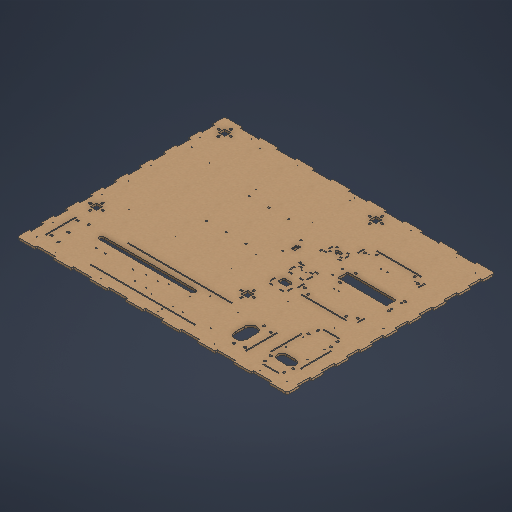
# Autodesk Inventor part: upper_base
Saved by Autodesk Inventor 2027.1 (Build 311270010, 270A)
## iProperties
Created: 2026-11-15
Part Number: upper_base
Material: MDF Medium Density Fiberboard
Document SubType Name: Modeling
Designer: SDS Scholar
Density: 0.8 g/cm^3
Appearance: Cardboard - Corrugated
Author: SDS Scholar
Autodesk Inventor part; units mm, degrees
(part 1 of 3)
ref_plane "YZ Plane" through (0, 0, 0) normal (1, 0, 0) x (0, 1, 0)
ref_plane "XZ Plane" through (0, 0, 0) normal (0, 1, 0) x (-1, 0, 0)
ref_plane "XY Plane" through (0, 0, 0) normal (0, 0, 1) x (1, 0, 0)
sketch "Sketch1" plane through (0, 0, 0) normal (0, 1, 0) x (-1, 0, 0)
  line L0 (-442.5, 340) -> (442.5, 340)
  line L1 (442.5, 340) -> (442.5, -340)
  line L2 (442.5, -340) -> (-442.5, -340)
  line L3 (-442.5, -340) -> (-442.5, 340)
  line L4 (-442.5, 340) -> (442.5, -340) construction
  line L5 (442.5, 340) -> (-442.5, -340) construction
  point P0 (0, 0)
  dimension "d0" = 680
  dimension "d1" = 885
  constraints: 12 end point, 2 midpoint, 2 parallel, 1 horizontal, 1 perpendicular
  measures "d0" distance of L0.end L1.end
  measures "d1" distance of L1.end L2.end
extrude "Extrusion1" add sketch "Sketch1" along normal blind 7
sketch "Sketch3" plane through (0, 7, 0) normal (0, 1, 0) x (1, 0, 0)
  line L0 (442.5, 340) -> (-442.5, 340) projected
  line L1 (-442.5, 340) -> (-442.5, -340) projected
  line L2 (-442.5, -340) -> (442.5, -340) projected
  line L3 (442.5, -340) -> (442.5, 340) projected
  line L4 (-407.5, 305) -> (107.5, 305)
  line L5 (107.5, 305) -> (107.5, -135)
  line L6 (107.5, -135) -> (-407.5, -135)
  line L7 (-407.5, -135) -> (-407.5, 305)
  line L8 (-407.5, 305) -> (-387.5, 305)
  line L9 (-387.5, 305) -> (-387.5, 285)
  line L10 (-387.5, 285) -> (-407.5, 285)
  line L11 (-407.5, 285) -> (-407.5, 305)
  line L12 (-407.5, 305) -> (-387.5, 285) construction
  line L13 (-387.5, 305) -> (-407.5, 285) construction
  line L14 (-397.5, 313.5) -> (-397.5, 316.5) construction
  line L15 (-394.6, 313.5) -> (-394.6, 316.5)
  line L16 (-400.4, 316.5) -> (-400.4, 313.5)
  arc A0 (-400.4, 313.5) -> (-394.6, 313.5) centre (-397.5, 313.5) ccw
  arc A1 (-394.6, 316.5) -> (-400.4, 316.5) centre (-397.5, 316.5) ccw
  line L17 (-407.5, 295) -> (-387.5, 295) construction
  line L18 (-397.5, 285) -> (-397.5, 305) construction
  line L19 (-397.5, 276.5) -> (-397.5, 273.5) construction
  line L20 (-394.6, 276.5) -> (-394.6, 273.5)
  line L21 (-400.4, 273.5) -> (-400.4, 276.5)
  arc A2 (-394.6, 276.5) -> (-400.4, 276.5) centre (-397.5, 276.5) ccw
  arc A3 (-400.4, 273.5) -> (-394.6, 273.5) centre (-397.5, 273.5) ccw
  line L22 (-416, 295) -> (-419, 295) construction
  line L23 (-416, 297.9) -> (-419, 297.9)
  line L24 (-419, 292.1) -> (-416, 292.1)
  arc A4 (-416, 292.1) -> (-416, 297.9) centre (-416, 295) ccw
  arc A5 (-419, 297.9) -> (-419, 292.1) centre (-419, 295) ccw
  line L25 (-379, 295) -> (-376, 295) construction
  line L26 (-379, 297.9) -> (-376, 297.9)
  line L27 (-376, 292.1) -> (-379, 292.1)
  arc A6 (-379, 297.9) -> (-379, 292.1) centre (-379, 295) ccw
  arc A7 (-376, 292.1) -> (-376, 297.9) centre (-376, 295) ccw
  line L28 (-387.5, -135) -> (-407.5, -135)
  line L29 (-387.5, -115) -> (-387.5, -135)
  line L30 (-407.5, -115) -> (-387.5, -115)
  line L31 (-407.5, -135) -> (-407.5, -115)
  arc A8 (-400.4, -106.5) -> (-394.6, -106.5) centre (-397.5, -106.5) ccw
  line L32 (-394.6, -106.5) -> (-394.6, -103.5)
  line L33 (-400.4, -103.5) -> (-400.4, -106.5)
  arc A9 (-394.6, -103.5) -> (-400.4, -103.5) centre (-397.5, -103.5) ccw
  arc A10 (-379, -122.1) -> (-379, -127.9) centre (-379, -125) ccw
  arc A11 (-376, -127.9) -> (-376, -122.1) centre (-376, -125) ccw
  line L34 (-376, -127.9) -> (-379, -127.9)
  line L35 (-379, -122.1) -> (-376, -122.1)
  arc A12 (-394.6, -143.5) -> (-400.4, -143.5) centre (-397.5, -143.5) ccw
  arc A13 (-400.4, -146.5) -> (-394.6, -146.5) centre (-397.5, -146.5) ccw
  line L36 (-400.4, -146.5) -> (-400.4, -143.5)
  line L37 (-394.6, -143.5) -> (-394.6, -146.5)
  arc A14 (-416, -127.9) -> (-416, -122.1) centre (-416, -125) ccw
  arc A15 (-419, -122.1) -> (-419, -127.9) centre (-419, -125) ccw
  line L38 (-416, -122.1) -> (-419, -122.1)
  line L39 (-419, -127.9) -> (-416, -127.9)
  line L40 (107.5, 285) -> (87.5, 285)
  line L41 (107.5, 305) -> (107.5, 285)
  line L42 (87.5, 305) -> (107.5, 305)
  line L43 (87.5, 285) -> (87.5, 305)
  arc A16 (94.6, 313.5) -> (100.4, 313.5) centre (97.5, 313.5) ccw
  line L44 (100.4, 313.5) -> (100.4, 316.5)
  line L45 (94.6, 316.5) -> (94.6, 313.5)
  arc A17 (100.4, 316.5) -> (94.6, 316.5) centre (97.5, 316.5) ccw
  arc A18 (116, 297.9) -> (116, 292.1) centre (116, 295) ccw
  arc A19 (119, 292.1) -> (119, 297.9) centre (119, 295) ccw
  line L46 (119, 292.1) -> (116, 292.1)
  line L47 (116, 297.9) -> (119, 297.9)
  arc A20 (100.4, 276.5) -> (94.6, 276.5) centre (97.5, 276.5) ccw
  arc A21 (94.6, 273.5) -> (100.4, 273.5) centre (97.5, 273.5) ccw
  line L48 (94.6, 273.5) -> (94.6, 276.5)
  line L49 (100.4, 276.5) -> (100.4, 273.5)
  arc A22 (79, 292.1) -> (79, 297.9) centre (79, 295) ccw
  arc A23 (76, 297.9) -> (76, 292.1) centre (76, 295) ccw
  line L50 (79, 297.9) -> (76, 297.9)
  line L51 (76, 292.1) -> (79, 292.1)
  line L52 (107.5, -135) -> (87.5, -135)
  line L53 (107.5, -115) -> (107.5, -135)
  line L54 (87.5, -115) -> (107.5, -115)
  line L55 (87.5, -135) -> (87.5, -115)
  arc A24 (94.6, -106.5) -> (100.4, -106.5) centre (97.5, -106.5) ccw
  line L56 (100.4, -106.5) -> (100.4, -103.5)
  line L57 (94.6, -103.5) -> (94.6, -106.5)
  arc A25 (100.4, -103.5) -> (94.6, -103.5) centre (97.5, -103.5) ccw
  arc A26 (116, -122.1) -> (116, -127.9) centre (116, -125) ccw
  arc A27 (119, -127.9) -> (119, -122.1) centre (119, -125) ccw
  line L58 (119, -127.9) -> (116, -127.9)
  line L59 (116, -122.1) -> (119, -122.1)
  arc A28 (100.4, -143.5) -> (94.6, -143.5) centre (97.5, -143.5) ccw
  arc A29 (94.6, -146.5) -> (100.4, -146.5) centre (97.5, -146.5) ccw
  line L60 (94.6, -146.5) -> (94.6, -143.5)
  line L61 (100.4, -143.5) -> (100.4, -146.5)
  arc A30 (79, -127.9) -> (79, -122.1) centre (79, -125) ccw
  arc A31 (76, -122.1) -> (76, -127.9) centre (76, -125) ccw
  line L62 (79, -122.1) -> (76, -122.1)
  line L63 (76, -127.9) -> (79, -127.9)
  point P0 (0, 0)
  point P1 (-397.5, 295)
  point P2 (-397.5, 315)
  point P3 (-397.5, 275)
  point P4 (-417.5, 295)
  point P5 (-397.5, 295)
  point P6 (-377.5, 295)
  point P7 (-397.5, -135)
  point P8 (-387.5, -125)
  point P9 (-397.5, -115)
  point P10 (-407.5, -125)
  point P11 (97.5, 285)
  point P12 (107.5, 295)
  point P13 (97.5, 305)
  point P14 (87.5, 295)
  point P15 (97.5, -135)
  point P16 (107.5, -125)
  point P17 (97.5, -115)
  point P18 (87.5, -125)
  point P19 (87.5, 305)
  point P20 (107.5, 285)
  point P21 (87.5, -135)
  point P22 (107.5, -115)
  point P23 (-407.5, -115)
  point P24 (-407.5, 285)
  dimension "d6" = 35
  dimension "d7" = 35
  dimension "d8" = 440
  dimension "d9" = 515
  dimension "d10" = 20
  dimension "d11" = 20
  dimension "d12" = 3
  dimension "d13" = 5.8
  dimension "d14" = 8.5
  dimension "d15" = 3
  dimension "d16" = 5.8
  dimension "d17" = 8.5
  dimension "d20" = 420
  dimension "d23" = 495
  constraints: 128 end point, 64 point on circle, 32 centre point, 14 symmetric about line, 9 midpoint, 8 tangent, 6 parallel, 4 horizontal, 3 perpendicular, 1 horizontal alignment, 1 vertical, 1 vertical alignment, 160 other
  measures "d6" distance between parallel lines of L0 L4
  measures "d7" distance between parallel lines of L1 L7
  measures "d8" distance of L6.end L4.start
  measures "d9" distance of L4.start L4.end
  measures "d10" distance of L4.start L10.end
  measures "d11" distance of L4.start L8.end
  measures "d12" distance of L14.start L14.end
  measures "d13" diameter of A1
  measures "d14" distance from line of L4 L14.start
  measures "d15" distance of L22.start L22.end
  measures "d16" diameter of A5
  measures "d17" distance from line of L7 L22.start
  measures "d20" distance of L9.end L28.start
  measures "d23" distance of L9.end L40.start
extrude "Extrusion2" cut sketch "Sketch3" against normal through all contours L4 L9 L10 L7 | L4 L5 L40 L43 | L30 L29 L6 L7 | L5 L6 L55 L54 | A0 L16 A1 L15 | L20 A3 L21 A2 | A4 L24 A5 L23 | L26 A7 L27 A6 | L33 A9 L32 A8 | L35 A11 L34 A10 | L37 A13 L36 A12 | L39 A15 L38 A14 | L45 A17 L44 A16 | L47 A19 L46 A18 | L49 A21 L48 A20 | L51 A23 L50 A22 | L57 A25 L56 A24 | L59 A27 L58 A26 | L61 A29 L60 A28 | L63 A31 L62 A30
sketch "Sketch4" plane through (0, 7, 0) normal (0, 1, 0) x (1, 0, 0)
  line L0 (-407.5, -135) -> (-407.5, -115) projected
  line L1 (107.5, 305) -> (107.5, 285) projected
  line L2 (-407.5, -135) -> (107.5, -135)
  line L3 (107.5, -135) -> (107.5, 305)
  line L4 (107.5, 305) -> (-407.5, 305)
  line L5 (-407.5, 305) -> (-407.5, -135)
  circle A0 centre (-177.5, 155) radius 2.75
  circle A1 centre (-177.5, 15) radius 2.75
  circle A2 centre (-112.5, 155) radius 2.75
  circle A3 centre (-112.5, 15) radius 2.75
  circle A4 centre (-47.5, 155) radius 2.75
  circle A5 centre (-47.5, 15) radius 2.75
  line L6 (17.5, -135) -> (17.5, 305) construction
  line L7 (17.5, 85) -> (107.5, 85) construction
  circle A6 centre (32.5, 55.5) radius 2.75
  circle A7 centre (32.5, 114.5) radius 2.75
  point P0 (0, 0)
  dimension "d29" = 230
  dimension "d30" = 150
  dimension "d33" = 140
  dimension "d36" = 65
  dimension "d47" = 65
  dimension "d48" = 5.5
  dimension "d49" = 5.5
  dimension "d50" = 59
  dimension "d51" = 15
  constraints: 12 end point, 8 centre point, 2 horizontal, 2 midpoint, 2 parallel, 2 point on line, 2 vertical, 1 perpendicular, 1 symmetric about line, 11 other
  measures "d29" distance from line of L5 A0.centre
  measures "d30" distance from line of L4 A0.centre
  measures "d33" distance of A0.centre A1.centre
  measures "d36" distance of A0.centre A2.centre
  measures "d47" distance from line of L6 A5.centre
  measures "d48" diameter of A6
  measures "d49" diameter of A0
  measures "d50" distance of A7.centre A6.centre
  measures "d51" distance from line of L6 A6.centre
hole "Hole1" at (-177.5, 7, -15) at (-177.5, 7, -155) at (-47.5, 7, -155) at (-112.5, 7, -15) at (-47.5, 7, -15) at (-112.5, 7, -155) at (32.5, 7, -55.5) at (32.5, 7, -114.5) direction (0, -1, 0) diameter 5.5 end through all clearance for "Hex Head Cap Screw ISO 24017" size "M5" standard "ISO"
sketch "Sketch6" plane through (0, 0, 0) normal (0, -1, 0) x (1, 0, 0)
  circle A0 centre (32.5, -114.5) radius 2.75 projected
  circle A1 centre (32.5, -55.5) radius 2.75 projected
  circle A2 centre (-112.5, -155) radius 2.75 projected
  circle A3 centre (-47.5, -15) radius 2.75 projected
  circle A4 centre (-112.5, -15) radius 2.75 projected
  circle A5 centre (-47.5, -155) radius 2.75 projected
  circle A6 centre (-177.5, -155) radius 2.75 projected
  circle A7 centre (-177.5, -15) radius 2.75 projected
  line L0 (-387.5, -305) -> (-407.5, -305) projected
  line L1 (-407.5, -305) -> (-407.5, -285) projected
  line L2 (-407.5, -285) -> (-387.5, -285) projected
  line L3 (-387.5, -285) -> (-387.5, -305) projected
  arc A8 (-419, 127.9) -> (-419, 122.1) centre (-419, 125) ccw projected
  line L4 (-419, 127.9) -> (-416, 127.9) projected
  arc A9 (-416, 122.1) -> (-416, 127.9) centre (-416, 125) ccw projected
  line L5 (-416, 122.1) -> (-419, 122.1) projected
  arc A10 (94.6, 143.5) -> (100.4, 143.5) centre (97.5, 143.5) ccw projected
  line L6 (94.6, 143.5) -> (94.6, 146.5) projected
  arc A11 (100.4, 146.5) -> (94.6, 146.5) centre (97.5, 146.5) ccw projected
  line L7 (100.4, 146.5) -> (100.4, 143.5) projected
  line L8 (107.5, 135) -> (107.5, 115) projected
  line L9 (107.5, 115) -> (87.5, 115) projected
  line L10 (87.5, 115) -> (87.5, 135) projected
  line L11 (87.5, 135) -> (107.5, 135) projected
  arc A12 (94.6, -316.5) -> (100.4, -316.5) centre (97.5, -316.5) ccw projected
  line L12 (94.6, -316.5) -> (94.6, -313.5) projected
  arc A13 (100.4, -313.5) -> (94.6, -313.5) centre (97.5, -313.5) ccw projected
  line L13 (100.4, -313.5) -> (100.4, -316.5) projected
  arc A14 (76, -292.1) -> (76, -297.9) centre (76, -295) ccw projected
  line L14 (76, -292.1) -> (79, -292.1) projected
  arc A15 (79, -297.9) -> (79, -292.1) centre (79, -295) ccw projected
  line L15 (79, -297.9) -> (76, -297.9) projected
  arc A16 (116, 127.9) -> (116, 122.1) centre (116, 125) ccw projected
  line L16 (116, 127.9) -> (119, 127.9) projected
  arc A17 (119, 122.1) -> (119, 127.9) centre (119, 125) ccw projected
  line L17 (119, 122.1) -> (116, 122.1) projected
  line L18 (-407.5, 135) -> (-387.5, 135) projected
  line L19 (-387.5, 135) -> (-387.5, 115) projected
  line L20 (-387.5, 115) -> (-407.5, 115) projected
  line L21 (-407.5, 115) -> (-407.5, 135) projected
  arc A18 (-400.4, 143.5) -> (-394.6, 143.5) centre (-397.5, 143.5) ccw projected
  line L22 (-400.4, 143.5) -> (-400.4, 146.5) projected
  arc A19 (-394.6, 146.5) -> (-400.4, 146.5) centre (-397.5, 146.5) ccw projected
  line L23 (-394.6, 146.5) -> (-394.6, 143.5) projected
  arc A20 (-379, -292.1) -> (-379, -297.9) centre (-379, -295) ccw projected
  line L24 (-379, -292.1) -> (-376, -292.1) projected
  arc A21 (-376, -297.9) -> (-376, -292.1) centre (-376, -295) ccw projected
  line L25 (-376, -297.9) -> (-379, -297.9) projected
  arc A22 (-400.4, -276.5) -> (-394.6, -276.5) centre (-397.5, -276.5) ccw projected
  line L26 (-400.4, -276.5) -> (-400.4, -273.5) projected
  arc A23 (-394.6, -273.5) -> (-400.4, -273.5) centre (-397.5, -273.5) ccw projected
  line L27 (-394.6, -273.5) -> (-394.6, -276.5) projected
  arc A24 (-400.4, 103.5) -> (-394.6, 103.5) centre (-397.5, 103.5) ccw projected
  line L28 (-400.4, 103.5) -> (-400.4, 106.5) projected
  arc A25 (-394.6, 106.5) -> (-400.4, 106.5) centre (-397.5, 106.5) ccw projected
  line L29 (-394.6, 106.5) -> (-394.6, 103.5) projected
  arc A26 (76, 127.9) -> (76, 122.1) centre (76, 125) ccw projected
  line L30 (76, 127.9) -> (79, 127.9) projected
  arc A27 (79, 122.1) -> (79, 127.9) centre (79, 125) ccw projected
  line L31 (79, 122.1) -> (76, 122.1) projected
  arc A28 (116, -292.1) -> (116, -297.9) centre (116, -295) ccw projected
  line L32 (116, -292.1) -> (119, -292.1) projected
  arc A29 (119, -297.9) -> (119, -292.1) centre (119, -295) ccw projected
  line L33 (119, -297.9) -> (116, -297.9) projected
  line L34 (107.5, -285) -> (107.5, -305) projected
  line L35 (107.5, -305) -> (87.5, -305) projected
  line L36 (87.5, -305) -> (87.5, -285) projected
  line L37 (87.5, -285) -> (107.5, -285) projected
  arc A30 (94.6, -276.5) -> (100.4, -276.5) centre (97.5, -276.5) ccw projected
  line L38 (94.6, -276.5) -> (94.6, -273.5) projected
  arc A31 (100.4, -273.5) -> (94.6, -273.5) centre (97.5, -273.5) ccw projected
  line L39 (100.4, -273.5) -> (100.4, -276.5) projected
  arc A32 (94.6, 103.5) -> (100.4, 103.5) centre (97.5, 103.5) ccw projected
  line L40 (94.6, 103.5) -> (94.6, 106.5) projected
  arc A33 (100.4, 106.5) -> (94.6, 106.5) centre (97.5, 106.5) ccw projected
  line L41 (100.4, 106.5) -> (100.4, 103.5) projected
  arc A34 (-379, 127.9) -> (-379, 122.1) centre (-379, 125) ccw projected
  line L42 (-379, 127.9) -> (-376, 127.9) projected
  arc A35 (-376, 122.1) -> (-376, 127.9) centre (-376, 125) ccw projected
  line L43 (-376, 122.1) -> (-379, 122.1) projected
  line L44 (-419, -292.1) -> (-416, -292.1) projected
  arc A36 (-416, -297.9) -> (-416, -292.1) centre (-416, -295) ccw projected
  line L45 (-416, -297.9) -> (-419, -297.9) projected
  arc A37 (-419, -292.1) -> (-419, -297.9) centre (-419, -295) ccw projected
  line L46 (-400.4, -316.5) -> (-400.4, -313.5) projected
  arc A38 (-394.6, -313.5) -> (-400.4, -313.5) centre (-397.5, -313.5) ccw projected
  line L47 (-394.6, -313.5) -> (-394.6, -316.5) projected
  arc A39 (-400.4, -316.5) -> (-394.6, -316.5) centre (-397.5, -316.5) ccw projected
  line L48 (442.5, -340) -> (-442.5, -340) projected
  line L49 (442.5, 340) -> (442.5, -340) projected
  line L50 (-442.5, 340) -> (442.5, 340) projected
  line L51 (-442.5, -340) -> (-442.5, 340) projected
  circle A40 centre (125.5, -85) radius 25
  line L52 (125.5, -60) -> (125.5, -110) construction
  line L53 (155.5, -40) -> (95.5, -40)
  line L54 (95.5, -40) -> (95.5, 60)
  line L55 (95.5, 60) -> (155.5, 60)
  line L56 (155.5, 60) -> (155.5, -40)
  line L57 (155.5, 57) -> (95.5, 57) construction
  line L58 (152.5, 60) -> (152.5, -40) construction
  line L59 (98.5, 60) -> (98.5, -40) construction
  line L60 (125.5, -40) -> (125.5, 60) construction
  line L61 (155.5, 10) -> (95.5, 10) construction
  line L62 (133, -40) -> (118, -40)
  line L63 (118, -40) -> (118, -37)
  line L64 (118, -37) -> (133, -37)
  line L65 (133, -37) -> (133, -40)
  line L66 (133, -37) -> (152.5, -37) construction
  line L67 (147.75, -40) -> (137.75, -40)
  line L68 (137.75, -40) -> (137.75, -37)
  line L69 (137.75, -37) -> (147.75, -37)
  line L70 (147.75, -37) -> (147.75, -40)
  line L71 (155.5, -7) -> (98.5, -7) construction
  line L72 (155.5, -4) -> (98.5, -4) construction
  line L73 (147.75, -7) -> (137.75, -7)
  line L74 (137.75, -7) -> (137.75, -4)
  line L75 (137.75, -4) -> (147.75, -4)
  line L76 (147.75, -4) -> (147.75, -7)
  line L77 (147.75, 57) -> (137.75, 57)
  line L78 (137.75, 57) -> (137.75, 60)
  line L79 (137.75, 60) -> (147.75, 60)
  line L80 (147.75, 60) -> (147.75, 57)
  line L81 (155.5, -29.5) -> (152.5, -29.5)
  line L82 (152.5, -29.5) -> (152.5, -14.5)
  line L83 (152.5, -14.5) -> (155.5, -14.5)
  line L84 (155.5, -14.5) -> (155.5, -29.5)
  line L85 (152.5, -40) -> (152.5, 60) construction
  line L86 (152.5, 34.5) -> (155.5, 34.5)
  line L87 (152.5, 49.5) -> (152.5, 34.5)
  line L88 (155.5, 49.5) -> (152.5, 49.5)
  line L89 (98.5, -14.5) -> (95.5, -14.5)
  line L90 (98.5, -29.5) -> (98.5, -14.5)
  line L91 (95.5, -29.5) -> (98.5, -29.5)
  line L92 (98.5, 34.5) -> (95.5, 34.5)
  line L93 (98.5, 49.5) -> (98.5, 34.5)
  line L94 (95.5, 49.5) -> (98.5, 49.5)
  line L95 (103.25, 60) -> (103.25, 57)
  line L96 (103.25, 57) -> (113.25, 57)
  line L97 (113.25, 57) -> (113.25, 60)
  line L98 (113.25, -7) -> (113.25, -4)
  line L99 (103.25, -4) -> (103.25, -7)
  line L100 (103.25, -7) -> (113.25, -7)
  line L101 (113.25, -4) -> (103.25, -4)
  line L102 (103.25, -37) -> (103.25, -40)
  line L103 (113.25, -37) -> (103.25, -37)
  line L104 (113.25, -40) -> (113.25, -37)
  line L105 (135.5, 40) -> (115.5, 40)
  line L106 (110.5, 35) -> (110.5, 25)
  line L107 (115.5, 20) -> (135.5, 20)
  line L108 (140.5, 25) -> (140.5, 35)
  arc A41 (140.5, 35) -> (135.5, 40) centre (135.5, 35) ccw
  arc A42 (135.5, 20) -> (140.5, 25) centre (135.5, 25) ccw
  arc A43 (110.5, 25) -> (115.5, 20) centre (115.5, 25) ccw
  arc A44 (115.5, 40) -> (110.5, 35) centre (115.5, 35) ccw
  line L109 (153.5, -130) -> (97.5, -130)
  line L110 (97.5, -130) -> (97.5, -156)
  line L111 (97.5, -156) -> (153.5, -156)
  line L112 (153.5, -156) -> (153.5, -130)
  line L113 (156.5, -130) -> (100.5, -130)
  line L114 (100.5, -130) -> (100.5, -156)
  line L115 (100.5, -156) -> (156.5, -156)
  line L116 (156.5, -156) -> (156.5, -130)
  line L117 (100.5, -138) -> (103.5, -138)
  line L118 (103.5, -138) -> (103.5, -148)
  line L119 (103.5, -148) -> (100.5, -148)
  line L120 (100.5, -148) -> (100.5, -138)
  line L121 (128.5, -130) -> (128.5, -156) construction
  line L122 (108, -130) -> (113, -130)
  line L123 (113, -130) -> (113, -133)
  line L124 (113, -133) -> (108, -133)
  line L125 (108, -133) -> (108, -130)
  line L126 (113, -156) -> (108, -156)
  line L127 (108, -156) -> (108, -153)
  line L128 (108, -153) -> (113, -153)
  line L129 (113, -153) -> (113, -156)
  line L130 (144, -130) -> (144, -133)
  line L131 (144, -133) -> (149, -133)
  line L132 (149, -133) -> (149, -130)
  line L133 (144, -153) -> (144, -156)
  line L134 (149, -153) -> (144, -153)
  line L135 (149, -156) -> (149, -153)
  line L136 (153.5, -148) -> (156.5, -148)
  line L137 (156.5, -138) -> (153.5, -138)
  line L138 (153.5, -138) -> (153.5, -148)
  line L139 (125.5, -156) -> (125.5, -130) construction
  line L140 (134.5, -147) -> (122.5, -147)
  line L141 (122.5, -139) -> (134.5, -139)
  arc A45 (134.5, -147) -> (138.5, -143) centre (134.5, -143) ccw
  arc A46 (138.5, -143) -> (134.5, -139) centre (134.5, -143) ccw
  arc A47 (122.5, -139) -> (118.5, -143) centre (122.5, -143) ccw
  arc A48 (118.5, -143) -> (122.5, -147) centre (122.5, -143) ccw
  circle A49 centre (132.41, -31.5) radius 1.25
  circle A50 centre (118.59, -31.5) radius 1.25
  line L142 (130.5, -136) -> (126.5, -136)
  line L143 (126.5, -136) -> (126.5, -133)
  line L144 (126.5, -133) -> (130.5, -133)
  line L145 (130.5, -133) -> (130.5, -136)
  line L146 (32.5, -55.5) -> (32.5, -114.5) construction
  circle A51 centre (55.5, -85) radius 25
  line L147 (39.5, -77.5) -> (42.5, -77.5)
  line L148 (42.5, -77.5) -> (42.5, -92.5)
  line L149 (42.5, -92.5) -> (39.5, -92.5)
  line L150 (39.5, -92.5) -> (39.5, -77.5)
  line L151 (44.5, -75) -> (51.5, -75)
  line L152 (51.5, -75) -> (51.5, -95)
  line L153 (51.5, -95) -> (44.5, -95)
  line L154 (44.5, -95) -> (44.5, -75)
  point P0 (0, 0)
  point P1 (125.5, 10)
  point P2 (125.5, -37)
  point P3 (125.5, 10)
  point P4 (142.75, -37)
  point P5 (142.75, -37)
  point P6 (142.75, -7)
  point P7 (142.75, 57)
  point P8 (155.5, -22)
  point P9 (140.5, 40)
  point P10 (110.5, 20)
  point P11 (140.5, 20)
  point P12 (125.5, 20)
  point P13 (100.5, -143)
  point P14 (156.5, -143)
  point P15 (103.5, -143)
  point P16 (110.5, -133)
  point P17 (110.5, -153)
  point P18 (138.5, -147)
  point P19 (118.5, -139)
  point P20 (138.5, -139)
  point P21 (153.5, -143)
  point P22 (128.5, -139)
  point P23 (128.5, -133)
  point P24 (125.5, -143)
  point P25 (128.5, -143)
  point P26 (153.5, -143)
  point P27 (128.5, -136)
  point P28 (32.5, -85)
  point P29 (144, -156)
  point P30 (149, -156)
  point P31 (138.5, -143)
  point P32 (108, -156)
  point P33 (113, -156)
  point P34 (95.5, -14.5)
  point P35 (95.5, -29.5)
  point P36 (103.25, -40)
  point P37 (113.25, -40)
  point P38 (137.75, -40)
  point P39 (118, -40)
  point P40 (155.5, 34.5)
  point P41 (155.5, 49.5)
  point P42 (113.25, 60)
  point P43 (103.25, 60)
  point P44 (95.5, 49.5)
  point P45 (95.5, 34.5)
  point P46 (39.5, -85)
  point P47 (44.5, -85)
  dimension "d100" = 50
  dimension "d101" = 100
  dimension "d102" = 60
  dimension "d103" = 45
  dimension "d104" = 3
  dimension "d105" = 3
  dimension "d106" = 3
  dimension "d107" = 3
  dimension "d108" = 15
  dimension "d109" = 10
  dimension "d110" = 3
  dimension "d111" = 30
  dimension "d112" = 10
  dimension "d113" = 10
  dimension "d114" = 15
  dimension "d115" = 18
  dimension "d116" = 30
  dimension "d117" = 20
  dimension "d118" = 20
  dimension "d119" = 5
  dimension "d120" = 56
  dimension "d121" = 26
  dimension "d122" = 90
  dimension "d123" = 56
  dimension "d124" = 26
  dimension "d125" = 10
  dimension "d126" = 3
  dimension "d127" = 5
  dimension "d128" = 3
  dimension "d129" = 10
  dimension "d130" = 5
  dimension "d131" = 3
  dimension "d132" = 10
  dimension "d133" = 20
  dimension "d134" = 8
  dimension "d135" = 4
  dimension "d136" = 2.5
  dimension "d137" = 2.5
  dimension "d138" = 11.32
  dimension "d139" = 8.5
  dimension "d140" = 4
  dimension "d141" = 3
  dimension "d142" = 3
  dimension "d143" = 3
  dimension "d144" = 6
  dimension "d263" = 50
  dimension "d264" = 23
  dimension "d265" = 29.5
  dimension "d266" = 70
  dimension "d327" = 15
  dimension "d328" = 3
  dimension "d329" = 7
  dimension "d331" = 2
  dimension "d332" = 7
  dimension "d333" = 20
  constraints: 206 end point, 39 symmetric about line, 33 midpoint, 33 point on line, 32 parallel, 21 perpendicular, 18 point on circle, 17 horizontal, 12 centre point, 12 tangent, 7 vertical alignment, 6 equal radius, 6 horizontal alignment, 3 vertical, 1 coincident, 14 other
  measures "d100" diameter of A40
  measures "d101" distance of L55.end L53.start
  measures "d102" distance of L53.start L53.end
  measures "d103" distance from line of L53 A40.centre
  measures "d104" distance between parallel lines of L56 L58
  measures "d105" distance between parallel lines of L55 L57
  measures "d106" distance between parallel lines of L54 L59
  measures "d107" distance of L66.start L62.start
  measures "d108" distance of L63.end L66.start
  measures "d109" distance of L69.start L69.end
  measures "d110" distance between parallel lines of L71 L72
  measures "d111" distance between parallel lines of L66 L71
  measures "d112" distance of L73.start L73.end
  measures "d113" distance of L77.start L77.end
  measures "d114" distance of L82.start L83.start
  measures "d115" distance from line of L53 point (155.5, -22)
  measures "d116" distance of point (110.5, 20) point (140.5, 20)
  measures "d117" distance of point (140.5, 20) point (140.5, 40)
  measures "d118" distance between parallel lines of L105 L55
  measures "d119" radius of A41
  measures "d120" distance of L109.start L109.end
  measures "d121" distance of L109.end L111.start
  measures "d122" distance between parallel lines of L53 L109
  measures "d123" distance of L113.start L113.end
  measures "d124" distance of L113.end L115.start
  measures "d125" distance of L117.end L118.end
  measures "d126" distance of L117.start L117.end
  measures "d127" distance of L123.end L124.end
  measures "d128" distance of L124.end L122.start
  measures "d129" distance from line of L114 point (110.5, -133)
  measures "d130" distance of L128.start L129.start
  measures "d131" distance of L126.end L128.start
  measures "d132" distance from line of L114 point (110.5, -153)
  measures "d133" distance of point (118.5, -139) point (138.5, -139)
  measures "d134" distance of point (138.5, -139) point (138.5, -147)
  measures "d135" radius of A45
  measures "d136" diameter of A49
  measures "d137" diameter of A50
  measures "d139" distance from line of L53 A49.centre
  measures "d140" distance of L143.end L145.start
  measures "d141" distance of L145.start L145.end
  measures "d142" distance between parallel lines of L109 L144
  measures "d143" distance of point (125.5, -143) point (128.5, -143)
  measures "d144" distance of A45.centre point (128.5, -143)
  measures "d263" diameter of A51
  measures "d264" horizontal distance of L146.end A51.centre
  measures "d265" vertical distance of L146.end A51.centre
  measures "d266" distance of A40.centre A51.centre
  measures "d327" distance of L149.end L147.start
  measures "d328" distance of L147.start L147.end
  measures "d329" distance between parallel lines of L146 L150
  measures "d331" distance between parallel lines of L148 L154
  measures "d332" distance of L151.start L151.end
  measures "d333" distance of L151.end L152.end
extrude "Extrusion3" cut sketch "Sketch6" against normal through all contours L53 L68 L69 L70 | L81 L82 L83 L56 | L86 L87 L88 L56 | L53 L102 L103 L104 | L80 L77 L78 L55 | L54 L89 L90 L91 | L97 L96 L95 L55 | L54 L94 L93 L92 | L73 L74 L75 L76 | L100 L99 L101 L98 | A41 L108 A42 L107 A43 L106 A44 L105 | L132 L131 L130 L109 | L137 L116 L136 L112 | L123 L124 L125 L109 | L111 L133 L134 L135 | L117 L118 L119 L114 | L111 L127 L128 L129 | L140 A48 A47 L141 A46 A45 | A49 | A50 | L142 L143 L144 L145 | L147 L148 L149 L150 | L151 L152 L153 L154
sketch "Sketch7" plane through (0, 7, 0) normal (0, 1, 0) x (1, 0, 0)
  circle A0 centre (32.5, 114.5) radius 2.75 projected
  circle A1 centre (32.5, 55.5) radius 2.75 projected
  line L0 (32.5, 114.5) -> (32.5, 55.5) construction
  line L1 (32.5, 85) -> (442.5, 85) construction
  line L2 (442.5, -340) -> (442.5, 340) projected
  line L3 (160, 210) -> (360, 210)
  line L4 (360, 210) -> (360, -40)
  line L5 (360, -40) -> (160, -40)
  line L6 (160, -40) -> (160, 210)
  circle A2 centre (125.5, 85) radius 25
  line L7 (357, 207) -> (163, 207)
  line L8 (163, 207) -> (163, -37)
  line L9 (163, -37) -> (357, -37)
  line L10 (357, -37) -> (357, 207)
  line L11 (187.5, 210) -> (332.5, 210)
  line L12 (332.5, 210) -> (332.5, 207)
  line L13 (332.5, 207) -> (187.5, 207)
  line L14 (187.5, 207) -> (187.5, 210)
  line L15 (332.5, -40) -> (332.5, -37)
  line L16 (187.5, -37) -> (187.5, -40)
  line L17 (357, 193.5) -> (360, 193.5)
  line L18 (360, 193.5) -> (360, 173.5)
  line L19 (360, 173.5) -> (357, 173.5)
  line L20 (357, 173.5) -> (357, 193.5)
  line L21 (357, -23.5) -> (360, -23.5)
  line L22 (360, -3.5) -> (357, -3.5)
  line L23 (260, 207) -> (260, -37) construction
  line L24 (163, 193.5) -> (160, 193.5)
  line L25 (160, 173.5) -> (163, 173.5)
  line L26 (160, -3.5) -> (163, -3.5)
  line L27 (163, -23.5) -> (160, -23.5)
  line L28 (348.5, 183.5) -> (345.5, 183.5) construction
  line L29 (348.5, 186.4) -> (345.5, 186.4)
  line L30 (345.5, 180.6) -> (348.5, 180.6)
  arc A3 (348.5, 180.6) -> (348.5, 186.4) centre (348.5, 183.5) ccw
  arc A4 (345.5, 186.4) -> (345.5, 180.6) centre (345.5, 183.5) ccw
  line L31 (348.5, -13.5) -> (345.5, -13.5) construction
  line L32 (348.5, -16.4) -> (345.5, -16.4)
  line L33 (345.5, -10.6) -> (348.5, -10.6)
  arc A5 (348.5, -16.4) -> (348.5, -10.6) centre (348.5, -13.5) ccw
  arc A6 (345.5, -10.6) -> (345.5, -16.4) centre (345.5, -13.5) ccw
  line L34 (171.5, 183.5) -> (174.5, 183.5) construction
  line L35 (171.5, 186.4) -> (174.5, 186.4)
  line L36 (174.5, 180.6) -> (171.5, 180.6)
  arc A7 (171.5, 186.4) -> (171.5, 180.6) centre (171.5, 183.5) ccw
  arc A8 (174.5, 180.6) -> (174.5, 186.4) centre (174.5, 183.5) ccw
  line L37 (174.5, -10.6) -> (171.5, -10.6)
  line L38 (171.5, -13.5) -> (174.5, -13.5) construction
  arc A9 (171.5, -10.6) -> (171.5, -16.4) centre (171.5, -13.5) ccw
  line L39 (171.5, -16.4) -> (174.5, -16.4)
  arc A10 (174.5, -16.4) -> (174.5, -10.6) centre (174.5, -13.5) ccw
  line L40 (322, 198.5) -> (322, 195.5) construction
  line L41 (319.1, 198.5) -> (319.1, 195.5)
  line L42 (324.9, 195.5) -> (324.9, 198.5)
  arc A11 (324.9, 198.5) -> (319.1, 198.5) centre (322, 198.5) ccw
  arc A12 (319.1, 195.5) -> (324.9, 195.5) centre (322, 195.5) ccw
  line L43 (198, 198.5) -> (198, 195.5) construction
  line L44 (200.9, 198.5) -> (200.9, 195.5)
  line L45 (195.1, 195.5) -> (195.1, 198.5)
  arc A13 (200.9, 198.5) -> (195.1, 198.5) centre (198, 198.5) ccw
  arc A14 (195.1, 195.5) -> (200.9, 195.5) centre (198, 195.5) ccw
  line L46 (322, -28.5) -> (322, -25.5) construction
  line L47 (319.1, -28.5) -> (319.1, -25.5)
  line L48 (324.9, -25.5) -> (324.9, -28.5)
  arc A15 (319.1, -28.5) -> (324.9, -28.5) centre (322, -28.5) ccw
  arc A16 (324.9, -25.5) -> (319.1, -25.5) centre (322, -25.5) ccw
  line L49 (200.9, -28.5) -> (200.9, -25.5)
  line L50 (198, -28.5) -> (198, -25.5) construction
  arc A17 (200.9, -25.5) -> (195.1, -25.5) centre (198, -25.5) ccw
  arc A18 (195.1, -28.5) -> (200.9, -28.5) centre (198, -28.5) ccw
  line L51 (195.1, -25.5) -> (195.1, -28.5)
  circle A19 centre (55.5, 85) radius 25
  point P0 (0, 0)
  point P1 (160, 85)
  point P2 (260, 210)
  point P3 (357, 183.5)
  point P4 (347, 183.5)
  point P5 (347, -13.5)
  point P6 (173, 183.5)
  point P7 (173, -13.5)
  point P8 (322, 197)
  point P9 (198, 197)
  point P10 (322, -27)
  point P11 (198, -27)
  point P12 (163, -3.5)
  point P13 (160, -3.5)
  point P14 (160, -23.5)
  point P15 (163, -23.5)
  point P16 (360, -23.5)
  point P17 (360, -3.5)
  point P18 (332.5, -40)
  point P19 (332.5, -37)
  point P20 (187.5, -37)
  point P21 (187.5, -40)
  point P22 (360, 193.5)
  point P23 (187.5, 207)
  point P24 (332.5, 210)
  point P25 (160, 173.5)
  point P26 (160, 193.5)
  dimension "d151" = 250
  dimension "d152" = 200
  dimension "d153" = 50
  dimension "d154" = 34.5
  dimension "d155" = 3
  dimension "d156" = 145
  dimension "d157" = 20
  dimension "d158" = 23.5
  dimension "d159" = 3
  dimension "d160" = 5.8
  dimension "d161" = 8.5
  dimension "d162" = 3
  dimension "d163" = 5.8
  dimension "d164" = 8.5
  dimension "d165" = 35
  dimension "d267" = 50
  dimension "d268" = 23
  dimension "d269" = 70
  constraints: 118 end point, 58 symmetric about line, 32 point on circle, 18 centre point, 10 parallel, 9 midpoint, 8 tangent, 7 point on line, 5 perpendicular, 4 horizontal, 2 horizontal alignment, 2 vertical, 15 other
  measures "d151" distance of L3.end L4.end
  measures "d152" distance of L3.start L3.end
  measures "d153" diameter of A2
  measures "d154" distance from line of L6 A2.centre
  measures "d155" distance between parallel lines of L3 L7
  measures "d156" distance between parallel lines of L12 L14
  measures "d157" distance between parallel lines of L17 L19
  measures "d158" distance from line of L7 point (357, 183.5)
  measures "d159" distance of L28.start L28.end
  measures "d160" diameter of A4
  measures "d161" distance from line of L10 L28.start
  measures "d162" distance of L40.start L40.end
  measures "d163" diameter of A12
  measures "d164" distance from line of L7 L40.start
  measures "d165" distance between parallel lines of L10 L40
  measures "d267" diameter of A19
  measures "d268" horizontal distance of L0.start A19.centre
  measures "d269" distance of A2.centre A19.centre
extrude "Extrusion4" cut sketch "Sketch7" against normal through all contours L3 L12 L7 L14 | L24 L8 L25 L6 | L26 L8 L27 L6 | L4 L19 L10 L17 | L4 L21 L10 L22 | L16 L9 L15 L5 | A3 L30 A4 L29 | L32 A6 L33 A5 | L35 A8 L36 A7 | A10 L39 A9 L37 | A11 L42 A12 L41 | L44 A14 L45 A13 | L47 A16 L48 A15 | A18 L51 A17 L49
sketch "Sketch8" plane through (0, 7, 0) normal (0, 1, 0) x (1, 0, 0)
  circle A0 centre (32.5, 114.5) radius 2.75 projected
  circle A1 centre (32.5, 55.5) radius 2.75 projected
  line L0 (32.5, 55.5) -> (32.5, 114.5) construction
  line L1 (32.5, 85) -> (442.5, 85) construction
  line L2 (442.5, -340) -> (442.5, 340) projected
  circle A2 centre (127.5, 85) radius 25
  line L3 (177.5, 107.5) -> (380.1, 107.5)
  line L4 (380.1, 107.5) -> (380.1, 62.5)
  line L5 (380.1, 62.5) -> (177.5, 62.5)
  line L6 (177.5, 62.5) -> (177.5, 107.5)
  line L7 (278.8, 107.5) -> (278.8, 60) construction
  circle A3 centre (375.1, 101) radius 2.5
  circle A4 centre (375.1, 69) radius 2.5
  circle A5 centre (182.5, 101) radius 2.5
  circle A6 centre (182.5, 69) radius 2.5
  circle A7 centre (55.5, 85) radius 25
  circle A8 centre (224, 32) radius 1.5
  circle A9 centre (239, 32) radius 1.5
  circle A10 centre (245, 165) radius 2
  circle A11 centre (265, 165) radius 2
  line L8 (163, 193.5) -> (163, 173.5) projected
  point P0 (0, 0)
  point P1 (177.5, 85)
  dimension "d168" = 50
  dimension "d169" = 45
  dimension "d170" = 202.6
  dimension "d171" = 50
  dimension "d172" = 5
  dimension "d173" = 6.5
  dimension "d174" = 5
  dimension "d270" = 50
  dimension "d271" = 23
  dimension "d272" = 72
  dimension "d395" = 3
  dimension "d396" = 3
  dimension "d397" = 15
  dimension "d398" = 30.5
  dimension "d399" = 46.5
  dimension "d400" = 4
  dimension "d401" = 4
  dimension "d402" = 20
  dimension "d403" = 57.5
  dimension "d404" = 82
  constraints: 14 end point, 10 centre point, 3 horizontal alignment, 3 midpoint, 3 point on line, 3 symmetric about line, 2 horizontal, 2 parallel, 2 vertical, 1 perpendicular, 3 other
  measures "d168" diameter of A2
  measures "d169" distance of L5.end L3.start
  measures "d170" distance of L3.start L3.end
  measures "d171" distance from line of A2.centre L6
  measures "d172" diameter of A3
  measures "d173" distance from line of L3 A3.centre
  measures "d174" distance from line of L4 A3.centre
  measures "d270" diameter of A7
  measures "d271" horizontal distance of L0.end A7.centre
  measures "d272" distance of A2.centre A7.centre
  measures "d395" diameter of A8
  measures "d396" diameter of A9
  measures "d397" distance of A9.centre A8.centre
  measures "d398" distance from line of L5 A9.centre
  measures "d399" distance from line of A8.centre L6
  measures "d400" diameter of A10
  measures "d401" diameter of A11
  measures "d402" distance of A11.centre A10.centre
  measures "d403" distance from line of L3 A10.centre
  measures "d404" distance from line of L8 A10.centre
hole "Hole2" at (182.5, 7, -101) at (182.5, 7, -69) at (375.1, 7, -101) at (375.1, 7, -69) direction (0, -1, 0) diameter 5.8 end through all clearance for "Hex Head Cap Screw ISO 24017" size "M5" standard "ISO"
sketch "Sketch9" plane through (0, 7, 0) normal (0, 1, 0) x (1, 0, 0)
  circle A0 centre (182.5, 101) radius 2.9 projected
  circle A1 centre (182.5, 69) radius 2.9 projected
  circle A2 centre (375.1, 101) radius 2.9 projected
  circle A3 centre (375.1, 69) radius 2.9 projected
  line L0 (182.5, 101) -> (375.1, 101)
  line L1 (375.1, 101) -> (375.1, 69)
  line L2 (375.1, 69) -> (182.5, 69)
  line L3 (182.5, 69) -> (182.5, 101)
  line L4 (202.5, 101) -> (355.1, 101)
  line L5 (358.1, 98) -> (358.1, 72)
  line L6 (355.1, 69) -> (202.5, 69)
  line L7 (199.5, 72) -> (199.5, 98)
  arc A4 (202.5, 101) -> (199.5, 98) centre (202.5, 98) ccw
  arc A5 (199.5, 72) -> (202.5, 69) centre (202.5, 72) ccw
  arc A6 (355.1, 69) -> (358.1, 72) centre (355.1, 72) ccw
  arc A7 (358.1, 98) -> (355.1, 101) centre (355.1, 98) ccw
  point P0 (0, 0)
  point P1 (199.5, 101)
  point P2 (358.1, 69)
  point P3 (355.1, 101)
  point P4 (202.5, 101)
  point P5 (202.5, 69)
  point P6 (355.1, 69)
  dimension "d182" = 17
  dimension "d183" = 17
  dimension "d184" = 3
  dimension "d185" = 3
  constraints: 16 end point, 8 point on circle, 8 tangent, 6 point on line, 4 centre point, 4 parallel, 2 equal radius, 2 horizontal, 2 perpendicular
  measures "d182" distance between parallel lines of L3 L7
  measures "d183" distance between parallel lines of L1 L5
  measures "d184" radius of A4
  measures "d185" radius of A7
extrude "Extrusion5" cut sketch "Sketch9" against normal through all contours L0 A7 L5 A6 L2 A5 L7 A4